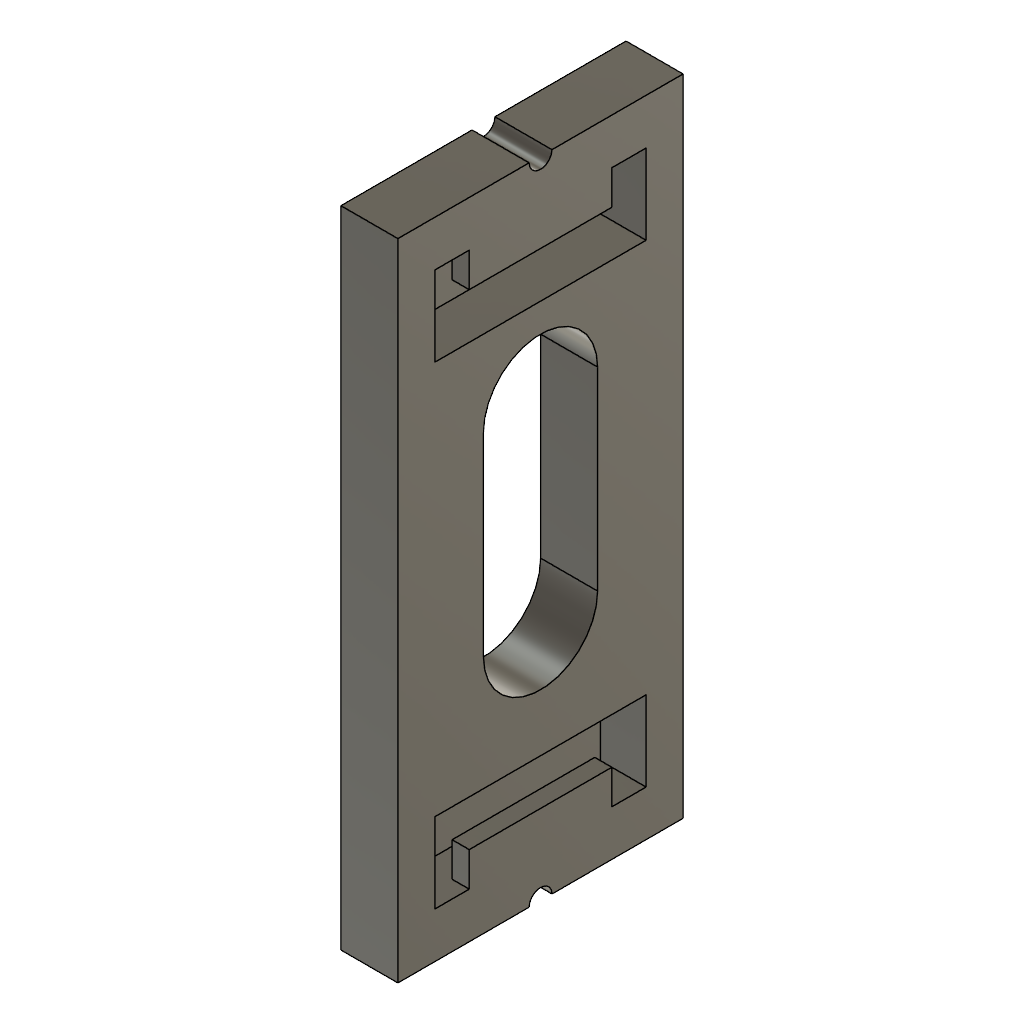
Door base (Autodesk Fusion 360 design; units mm, degrees)
part number: 2026-03-15-16-48-36-248
Autodesk Fusion 360 part; units mm, degrees
sketch "Sketch1" plane through (0, 0, 0) normal (1, 0, 0) x (0, 1, 0)
  line L0 (25, 115) -> (25, 2)
  line L1 (-25, 2) -> (-25, 115)
  line L2 (-25, 115) -> (-2, 115)
  line L3 (2, 115) -> (25, 115)
  arc A0 (-2, 115) -> (2, 115) centre (0, 115) ccw
  line L4 (0, 181) -> (0, 113)
  line L5 (-10, 78) -> (-10, 43.9973)
  arc A1 (-10, 43.9973) -> (10, 43.9973) centre (0, 43.9973) ccw
  line L6 (10, 43.9973) -> (10, 78)
  arc A2 (10, 78) -> (-10, 78) centre (0, 78) ccw
  line L7 (0, 88) -> (0, 33.9973) construction
  arc A3 (-4.2518, 2) -> (-1.9914, 1.9955) centre (3.545, 3346.3873) ccw
  line L8 (-4.2518, 2) -> (-1.9914, 2)
  line L9 (2.0086, 2) -> (25, 2)
  line L10 (-25, 2) -> (-1.9914, 2)
  line L11 (-1.9914, 2) -> (-25, 2)
  arc A4 (2.0086, 1.9958) -> (-1.9914, 1.9955) centre (0.0086, 1.9973) ccw
  line L12 (25, 2) -> (2.0086, 2)
  line L13 (-1.9914, 2) -> (-4.2518, 2)
  point P0 (-25, 58.5)
  point P1 (0, 58.5)
  point P2 (0.0086, 1.9973)
  point P3 (0.0084, 3.9973)
  dimension "d1" = 50
  dimension "d2" = 113
  dimension "d3" = 4
  dimension "d4" = 20
  dimension "d5" = 25
  dimension "d7" = 4
  dimension "d9" = 30
  constraint horizontal L2
  constraint vertical L0
  constraint horizontal L12
  constraint vertical L1
  constraint collinear L2 L3
  constraint coincident A0.centre L2
  constraint midpoint L1 P0
  constraint midpoint A0 L4.end
  constraint tangent L5 A1
  constraint tangent A1 L6
  constraint parallel L5 L6
  constraint tangent L6 A2
  constraint tangent L5 A2
  constraint midpoint A2 L7.start
  constraint midpoint A1 L7.end
  constraint vertical L7
  constraint coincident P2 A4.centre
  constraint coincident L8.end A4
  constraint coincident L9.start A4
  constraint collinear L8 L9
  constraint collinear L12 L13
  constraint midpoint A4 P3
  measures "d1" distance of L1.end L0.start
  measures "d2" distance of L1.end L1.start
  measures "d3" diameter of A0
  measures "d4" diameter of A1
  measures "d5" distance of L4.end L7.start
  measures "d7" diameter of A4
  measures "d9" vertical distance of L7.end P3
sketch "Sketch2" plane through (0, 0, 0) normal (1, 0, 0) x (0, 1, 0)
  line L0 (18.5, 107) -> (-18.5, 107)
  line L1 (-18.5, 107) -> (-18.5, 93)
  line L2 (-18.5, 93) -> (18.5, 93)
  line L3 (18.5, 93) -> (18.5, 107)
  line L4 (2, 115) -> (25, 115)
  line L5 (25, 115) -> (25, 2)
  line L6 (-25, 2) -> (-25, 115)
  line L7 (12.5, 93) -> (-12.5, 93)
  line L8 (-12.5, 10) -> (-12.5, 16)
  line L9 (18.5, 24) -> (-18.5, 24)
  line L10 (-12.5, 16) -> (12.5, 16)
  line L11 (12.5, 10) -> (-12.5, 10)
  line L12 (18.5, 10) -> (18.5, 24)
  line L13 (-18.5, 24) -> (-18.5, 10)
  line L14 (12.5, 16) -> (12.5, 10)
  line L15 (-18.5, 10) -> (18.5, 10)
  line L16 (2.0086, 2) -> (25, 2)
  line L17 (-12.5, 99) -> (-12.5, 107) construction
  line L18 (12.5, 99) -> (12.5, 107) construction
  line L19 (-12.5, 101) -> (12.5, 101)
  line L20 (-12.5, 101) -> (-12.5, 107)
  line L21 (12.5, 101) -> (12.5, 107)
  point P0 (0, 88)
  point P1 (0, 107)
  point P2 (0, 24)
  dimension "d12" = 8
  dimension "d13" = 5
  dimension "d14" = 37
  dimension "d15" = 6.5
  dimension "d16" = 6.5
  dimension "d22" = 37
  dimension "d23" = 6
  dimension "d24" = 25
  dimension "d25" = 8
  dimension "d39" = 6
  constraint horizontal L0
  constraint vertical L1
  constraint horizontal L2
  constraint vertical L3
  constraint midpoint L0 P1
  constraint horizontal L7
  constraint coincident L2 L7.start
  constraint horizontal L9
  constraint vertical L13
  constraint horizontal L15
  constraint vertical L12
  constraint midpoint P2 L9
  constraint horizontal L11
  constraint vertical L8
  constraint horizontal L10
  constraint vertical L14
  constraint coincident L11.start L15
  constraint coincident L0 L17.end
  constraint perpendicular L0 L17
  constraint coincident L0 L18.end
  constraint perpendicular L0 L18
  constraint perpendicular L0 L20
  constraint perpendicular L0 L21
  measures "d12" distance of L0 L4
  measures "d13" distance of L2 P0
  measures "d14" distance of L0.start L0.end
  measures "d15" distance of L3 L5
  measures "d16" distance of L1 L6
  measures "d22" distance of L9.start L9.end
  measures "d23" distance of L12 L14
  measures "d24" distance of L8 L14
  measures "d25" distance of L15 L16
  measures "d39" distance of L0 L19
extrude "Extrude1" add sketch "Sketch1" against normal blind 10 contours L0 L1 L2 L3 A0 L8 L9 L10 L11 A4 L12 L13
extrude "Extrude2" cut sketch "Sketch2" against normal blind 8 contours L0 L1 L2 L3 L7 L19 L20 L21
extrude "Extrude3" cut sketch "Sketch2" against normal blind 8 contours L8 L9 L10 L12 L13 L14 L15
move_body "Move1" bodies 1 to x (1, 0, 0) y (0, 1, 0) z (0, 0, 1) at (5, 0, 0)
extrude "Extrude4" cut sketch "Sketch2" along normal blind 2 contours L0 L1 L2 L3 L7 L19 L20 L21 | L0 L19 L20 L21
extrude "Extrude5" cut sketch "Sketch2" against normal blind 3 contours L0 L1 L2 L3 L7 L19 L20 L21 | L0 L19 L20 L21
extrude "Extrude6" cut sketch "Sketch2" along normal blind 2 contours L8 L10 L11 L14 L15
extrude "Extrude7" cut sketch "Sketch2" against normal blind 3 contours L8 L10 L11 L14 L15
